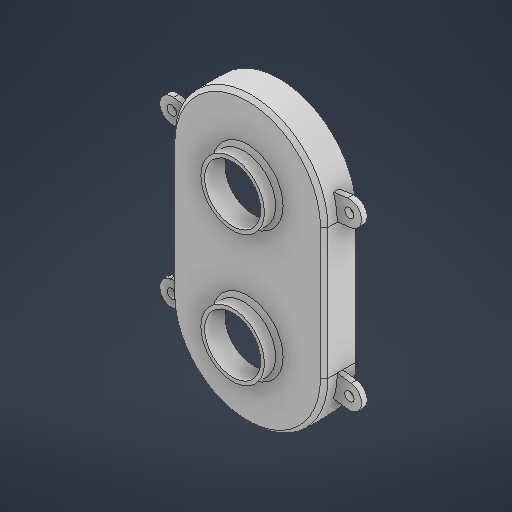
# Autodesk Inventor part: GuardaEngrenagens
Saved by Autodesk Inventor 2026.2 (Build 302298000, 298)
## iProperties
Created: 2026-10-30
Part Number: GuardaEngrenagens
Material: Genérico
Document SubType Name: Modeling
Designer: IFSP
Density: 1 g/cm^3
Appearance: Padrão
Author: IFSP
Autodesk Inventor part; units mm, degrees
ref_plane "YZ Plane" through (0, 0, 0) normal (1, 0, 0) x (0, 1, 0)
ref_plane "XZ Plane" through (0, 0, 0) normal (0, 1, 0) x (-1, 0, 0)
sketch "Esboço1" plane through (0, 0, 0) normal (0, 0, 1) x (1, 0, 0)
  line L0 (0, 35) -> (0, -35) construction
  line L1 (-41, 35) -> (-41, -35)
  line L2 (41, -35) -> (41, 35)
  arc A0 (41, 35) -> (-41, 35) centre (0, 35) ccw
  arc A1 (-41, -35) -> (41, -35) centre (0, -35) ccw
  point P0 (0, 0)
  constraints: 8 end point, 4 point on circle, 4 tangent, 2 centre point, 1 midpoint, 1 parallel, 1 vertical
extrude "Extrusão1" add sketch "Esboço1" along normal blind 17
shell "Casca1" thickness 2 removed faces 1 at (-13.6667, 11.6667, 0)
thicken "Espessar1" operation add thickness 1 both sides no extend neighbours no toward (0, 0, -1) faces at (-13, -11.6667, 15)
chamfer "Chanfro1" distance 2 angle 45 4 edges at (0, 76, 17) (-41, 0, 17) (0, -76, 17) (41, 0, 17)
sketch "Esboço2" plane through (0, 0, 17) normal (0, 0, 1) x (1, 0, 0)
  circle A0 centre (0, -35) radius 17
  arc A1 (-41, -35) -> (41, -35) centre (0, -35) ccw projected
  point P0 (0, 0)
  dimension "d12" = 34
  constraints: 1 centre point, 1 concentric
  measures "d12" diameter of A0
extrude "Extrusão2" add sketch "Esboço2" along normal blind 8
chamfer "Chanfro2" distance 2 angle 45 1 edges at (-17, -35, 17)
sketch "Esboço3" plane through (0, -35, 25) normal (0, 0, 1) x (1, 0, 0)
  circle A0 centre (0, 0) radius 17 projected
  point P0 (0, 35)
  constraints: 1 coincident
hole "Furo1" at (0, -35, 25) direction (0, 0, -1) diameter 30 end through all
sketch "Esboço7" plane through (0, 0, 17) normal (0, 0, 1) x (1, 0, 0)
  circle A0 centre (0, 35) radius 17
  arc A1 (39, 35) -> (-39, 35) centre (0, 35) ccw projected
  point P0 (0, 0)
  dimension "d35" = 34
  constraints: 1 centre point, 1 concentric
  measures "d35" diameter of A0
extrude "Extrusão3" add sketch "Esboço7" along normal blind 8
sketch "Esboço8" plane through (0, 35, 25) normal (0, 0, 1) x (1, 0, 0)
  circle A0 centre (0, 0) radius 17 projected
  point P0 (0, -35)
  constraints: 1 coincident
hole "Furo2" at (0, 35, 25) direction (0, 0, -1) diameter 30 end through all
chamfer "Chanfro3" distance 2 angle 45 1 edges at (-17, 35, 17)
ref_plane "Plano de trabalho7" through (0, 0, 7) normal (0, 0, -1) x (-1, 0, 0)
sketch "Esboço9" plane through (0, 0, 7) normal (0, 0, -1) x (-1, 0, 0)
  arc A0 (-41, -35) -> (41, -35) centre (0, -35) ccw projected
  line L0 (41, -35) -> (48.4239, -36.066)
  arc A1 (46.5761, -48.934) -> (48.4239, -36.066) centre (47.5, -42.5) ccw
  line L1 (46.5761, -48.934) -> (38.9385, -47.8373)
  point P0 (0, 0)
  dimension "d50" = 47.5
  dimension "d51" = 42.5
  dimension "d52" = 6.5
  constraints: 4 end point, 3 point on circle, 2 tangent, 1 centre point, 1 parallel
  measures "d50" horizontal distance of A0.centre A1.centre
  measures "d51" vertical distance of point (0, 0) A1.centre
  measures "d52" radius of A1
extrude "Extrusão4" add sketch "Esboço9" against normal blind 3
mirror "Espelhar1" about plane through (0, 0, 0) normal (1, 0, 0) of "Extrusão4"
mirror "Espelhar2" about plane through (0, 0, 0) normal (0, 1, 0) of "Extrusão4", "Espelhar1"
sketch "Esboço10" plane through (47.5, -42.5, 10) normal (0, 0, 1) x (0.9898477, -0.142132, 0)
  arc A0 (0, -6.5) -> (0, 6.5) centre (0, 0) ccw projected
  arc A1 (-10.2523, 77.8997) -> (-13.9102, 90.3744) centre (-12.0812, 84.1371) ccw projected
  arc A2 (-106.1168, 77.1345) -> (-106.1168, 64.1345) centre (-106.1168, 70.6345) ccw projected
  arc A3 (-95.8645, -7.2652) -> (-92.2066, -19.7399) centre (-94.0355, -13.5025) ccw projected
  circle A4 centre (-106.1168, 70.6345) radius 2.5
  circle A5 centre (-12.0812, 84.1371) radius 2.5
  circle A6 centre (0, 0) radius 2.5
  circle A7 centre (-94.0355, -13.5025) radius 2.5
  point P0 (-53.0584, 35.3173)
  constraints: 4 centre point, 4 coincident
extrude "Extrusão5" cut sketch "Esboço10" against normal blind 10
